Autodesk Fusion 360 part; units mm, degrees
(part 2 of 2)
component "PRINT 20 Call fork cheek B" placed x (1, 0, 0) y (0, 1, 0) z (0, 0, 1) at (0, 0, 0) in component "VS-MGE20 Case Assembly"
component "PRINT 21 End fork cheek A" placed x (1, 0, 0) y (0, 1, 0) z (0, 0, 1) at (0, 0, 0) in component "VS-MGE20 Case Assembly"
component "PRINT 22 End fork cheek B" placed x (1, 0, 0) y (0, 1, 0) z (0, 0, 1) at (0, 0, 0) in component "VS-MGE20 Case Assembly"
component "PRINT 23 Call follower pin" placed x (1, 0, 0) y (0, 1, 0) z (0, 0, 1) at (0, 0, 0) in component "VS-MGE20 Case Assembly"
component "PRINT 24 End follower pin" placed x (1, 0, 0) y (0, 1, 0) z (0, 0, 1) at (0, 0, 0) in component "VS-MGE20 Case Assembly"
component "TPU 01 Call button pad" placed x (1, 0, 0) y (0, 1, 0) z (0, 0, 1) at (0, 0, 0) in component "VS-MGE20 Case Assembly"
component "TPU 02 End button pad" placed x (1, 0, 0) y (0, 1, 0) z (0, 0, 1) at (0, 0, 0) in component "VS-MGE20 Case Assembly"
component "REFERENCE ONLY - DO NOT PRINT" placed x (1, 0, 0) y (0, 1, 0) z (0, 0, 1) at (0, 0, 0) in component "VS-MGE20 Case Assembly"
hidden bodies 57 58 59 60
equation "d7 = -( 6.00 mm )"
equation "d253 = -( 2.00 mm )"
equation "d257 = -( 2.00 mm )"
equation "d275 = -( 2.00 mm )"
equation "d279 = -( 2.00 mm )"
equation "d377 = -( 14.00 mm )"
equation "d385 = -( 14.00 mm )"
named bodies: "SG90 mount Call", "SG90 mount End"
